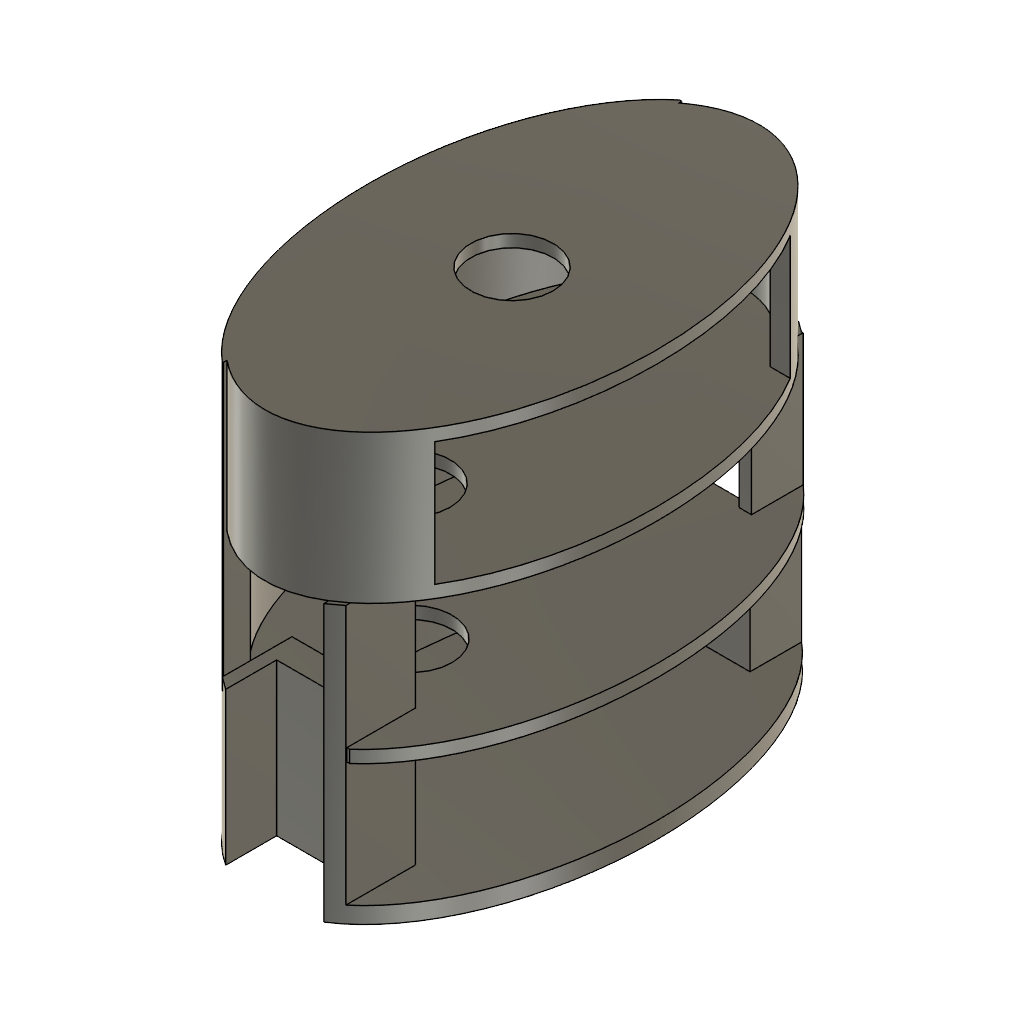
RobotBody (Autodesk Fusion 360 design; units mm, degrees)
part number: 2026-05-27-16-43-57-428
Autodesk Fusion 360 part; units mm, degrees
sketch "Sketch1" plane through (0, 0, 0) normal (0, 0, 1) x (1, 0, 0)
  line L0 (0, 45) -> (12, 45)
  line L1 (12, 45) -> (-12, 45)
  line L2 (-12, 45) -> (12.1326, 45)
  line L3 (12.1326, 45) -> (12.1326, 57.4523)
  line L4 (-12, 57.5375) -> (-12, 45)
  line L5 (-0.0989, -41.2502) -> (-12.0988, -41.3096)
  line L6 (-12.0988, -41.3096) -> (11.9009, -41.1909)
  line L7 (11.9009, -41.1909) -> (-11.9631, -41.1909)
  line L8 (-11.9631, -41.1909) -> (-11.9631, -57.561)
  line L9 (11.9009, -57.561) -> (11.9009, -41.1909)
  ellipse E0 centre (0, 0) end of major axis (35, 0) minor radius 61.25 (-12, 57.5375) -> (-11.9631, -57.561) ccw
  ellipse E1 centre (0, 0) end of major axis (35, 0) minor radius 61.25 (11.9009, -57.6005) -> (12.1326, 57.4523) ccw
  line L10 (11.9009, -41.1909) -> (11.9009, -57.6005)
  dimension "d1" = 70
  dimension "d2" = 122.5
  dimension "d3" = 12
  dimension "d4" = 24
  dimension "d6" = 12
  dimension "d7" = 24
  constraint coincident E0.centre E1.centre
  constraint horizontal L2
  constraint vertical L3
  constraint vertical L4
  constraint horizontal L7
  constraint vertical L8
  constraint vertical L9
  constraint concentric E0 E1
  constraint perpendicular L7 L10
  measures "d1" distance of E0
  measures "d3" distance of L0.start L0.end
  measures "d4" distance of L0.end L1.end
  measures "d6" distance of L5.start L5.end
  measures "d7" distance of L5.end L6.end
extrude "Extrude1" add sketch "Sketch1" along normal blind 4 contours L0 L1 L2 L3 L4 L7 L8 L9 E0 E1 L10
sketch "Sketch2" plane through (0, 0, 4) normal (0, 0, 1) x (-1, 0, 0)
  line L0 (11.9631, 41.1909) -> (-11.9009, 41.1909)
  line L1 (-11.9009, 41.1909) -> (-11.9009, 57.6005)
  ellipse E0 centre (0, 0) end of major axis (0, -61.25) minor radius 35 (-11.9009, 57.6005) -> (-12.1326, -57.4523) ccw
  line L2 (-12.1326, -57.4523) -> (-12.1326, -45)
  line L3 (-12.1326, -45) -> (12, -45)
  line L4 (12, -45) -> (12, -57.5375)
  ellipse E1 centre (0, 0) end of major axis (0, -61.25) minor radius 35 (12, -57.5375) -> (11.9631, 57.561) ccw
  line L5 (11.9631, 57.561) -> (11.9631, 41.1909)
  line L6 (14.7106, -42.8069) -> (-15, -42.8069)
  line L7 (-15, -42.8069) -> (-15, -55.3399)
  line L8 (14.7106, -55.5773) -> (14.7106, -42.8069)
  line L9 (-15, 38.4373) -> (15, 38.4373)
  line L10 (15, 38.4373) -> (15, 55.3399)
  line L11 (-15, 55.3399) -> (-15, 38.4373)
  constraint horizontal L6
  constraint vertical L7
  constraint vertical L8
  constraint horizontal L9
  constraint vertical L10
  constraint vertical L11
  constraint coincident E1 L8.start
  constraint coincident E0 L7.end
  constraint coincident E1 L10.end
  constraint coincident E0 L11.start
extrude "Extrude2" add sketch "Sketch2" along normal blind 20 contours L0 L1 E0 E1 L5 L9 L10 L11 | E0 L2 L3 L4 E1 L6 L7 L8
sketch "Sketch3" plane through (0, 0, 4) normal (0, 0, 1) x (-1, 0, 0)
  line L0 (15, 55.3399) -> (15, 38.4373)
  line L1 (15, 38.4373) -> (-15, 38.4373)
  line L2 (-15, 38.4373) -> (-15, 55.3399)
  ellipse E0 centre (0, 0) end of major axis (0, -61.25) minor radius 35 (-15, 55.3399) -> (-15, -55.3399) ccw
  line L3 (-15, -55.3399) -> (-15, -42.8069)
  line L4 (-15, -42.8069) -> (14.7106, -42.8069)
  line L5 (14.7106, -42.8069) -> (14.7106, -55.5773)
  ellipse E1 centre (0, 0) end of major axis (0, -61.25) minor radius 35 (14.7106, -55.5773) -> (15, 55.3399) ccw
  ellipse E2 centre (0, 0) end of major axis (-30, 0) minor radius 55 (14.7106, -47.9339) -> (15, 47.6314) ccw
  ellipse E3 centre (0, 0) end of major axis (-30, 0) minor radius 55 (-15, 47.6314) -> (-15, -47.6314) ccw
  constraint coincident E0.centre E1.centre
  constraint concentric E2 E3
extrude "Extrude3" add sketch "Sketch3" along normal blind 80 contours L0 L5 E1 E2
extrude "Extrude4" cut 1 faces at (-29.9367, -18.1524, 84) along direction (0, 0, -1) blind 40
extrude "Extrude5" cut 1 faces at (-29.9367, -18.1524, 44) along direction (0, 0, -1) blind 10
sketch "Sketch4" plane through (0, 0, 34) normal (0, 0, 1) x (-1, 0, 0)
  ellipse E0 centre (0, 0) end of major axis (0, -55) minor radius 30 (14.7106, -47.9339) -> (15, 47.6314) ccw
  line L0 (14.7106, -47.9339) -> (14.7106, -55.5773)
  ellipse E1 centre (0, 0) end of major axis (0, -61.25) minor radius 35 (14.7106, -55.5773) -> (15, 55.3399) ccw
  line L1 (15, 55.3399) -> (15, 47.6314)
  line L2 (15.3224, 37.9496) -> (-15.6787, 37.9496)
  line L3 (-15.6787, 37.9496) -> (-15.6787, 55.1146)
  line L4 (15.3224, 55.4246) -> (15.3224, 37.9496)
  line L5 (-15.1442, -42.4038) -> (14.7879, -42.4038)
  line L6 (14.7879, -42.4038) -> (14.7879, -55.8732)
  line L7 (-15.1442, -55.5763) -> (-15.1442, -42.4038)
  ellipse E2 centre (0, 0) end of major axis (35, 0) minor radius 61.6458 (-15.6787, 55.1146) -> (-15.1442, -55.5763) ccw
  ellipse E3 centre (0, 0) end of major axis (35, 0) minor radius 61.6458 (14.7879, -55.8732) -> (15.3224, 55.4246) ccw
  constraint coincident E0.centre E1.centre
  constraint horizontal L2
  constraint vertical L3
  constraint vertical L4
  constraint horizontal L5
  constraint vertical L6
  constraint vertical L7
  constraint concentric E2 E3
extrude "Extrude6" add sketch "Sketch4" along normal blind 3 contours E0 L2 L3 L4 L5 L6 L7 E2 | E0 E1 L4 L6
hole "Hole1" at (-0.0979, -24.4642, 37) direction (0, 0, -1) diameter 20 depth 25 tip angle 118
sketch "Sketch5" plane through (0, 0, 37) normal (0, 0, 1) x (-1, 0, 0)
  circle A0 centre (0.0979, 24.4642) radius 10
  line L0 (-15.1442, -42.4038) -> (14.7879, -42.4038)
  line L1 (14.7879, -42.4038) -> (14.7879, -55.5144)
  ellipse E0 centre (0, 0) end of major axis (0, -61.25) minor radius 35 (14.7879, -55.5144) -> (15.3224, 55.0687) ccw
  line L2 (15.3224, 55.0687) -> (15.3224, 37.9496)
  line L3 (15.3224, 37.9496) -> (-15.6787, 37.9496)
  line L4 (-15.6787, 37.9496) -> (-15.6787, 55.1146)
  ellipse E1 centre (0, 0) end of major axis (0, 61.6458) minor radius 35 (-15.6787, 55.1146) -> (-15.1442, -55.5763) ccw
  line L5 (-15.1442, -55.5763) -> (-15.1442, -42.4038)
  ellipse E2 centre (0, 0) end of major axis (30, 0) minor radius 56.4175 (14.7879, -49.0871) -> (15.3224, 48.5039) ccw
  constraint coincident E0.centre E1.centre
extrude "Extrude7" add sketch "Sketch5" along normal blind 30 contours L1 E0 L2 E2
sketch "Sketch6" plane through (0, 0, 67) normal (0, 0, 1) x (-1, 0, 0)
  ellipse E0 centre (0, 0) end of major axis (0, 56.4175) minor radius 30 (14.7879, -49.0871) -> (15.3224, 48.5039) ccw
  line L0 (14.7879, -49.0871) -> (14.7879, -55.5144)
  ellipse E1 centre (0, 0) end of major axis (0, -61.25) minor radius 35 (14.7879, -55.5144) -> (15.3224, 55.0687) ccw
  line L1 (15.3224, 55.0687) -> (15.3224, 48.5039)
  ellipse E2 centre (0, 0) end of major axis (35, 0) minor radius 60
  line L2 (-35, 0) -> (35, 0) construction
  line L3 (0, -60) -> (0, 60) construction
  circle A0 centre (0, 25) radius 10
  dimension "d25" = 20
  constraint coincident E2 L2.start
  constraint coincident E2 L2.end
  constraint coincident E2 L3.start
  constraint coincident E2 L3.end
  constraint coincident E0.centre E1.centre
  constraint horizontal L2
  constraint coincident L3 A0.centre
  measures "d25" diameter of A0
extrude "Extrude8" add sketch "Sketch6" along normal blind 3 contours E0 L0 L1 E2 | E0 L0 L1 E2
extrude "Extrude9" add 1 faces at (13.967, -44.9894, 24) along direction (0, 0, 1) blind 13
extrude "Extrude10" add 1 faces at (15.6787, -43.6712, 35) along direction (-1, 0, 0) blind 0.678
extrude "Extrude11" add 1 faces at (-5.2147, -37.9496, 36) along direction (0, -1, 0) blind 0.48
extrude "Extrude12" add 1 faces at (-15.3224, -52.5058, 47) along direction (1, 0, 0) blind 0.322
sketch "Sketch7" plane through (0, 0, 37) normal (0, 0, 1) x (-1, 0, 0)
  line L0 (-15, 55.3399) -> (-15, 38.4373)
  line L1 (-15, 38.4373) -> (15, 38.4373)
  line L2 (15, 38.4373) -> (15, 55.3399)
  ellipse E0 centre (0, 0) end of major axis (0, -61.25) minor radius 35 (15, 55.3399) -> (11.9631, 57.561) ccw
  line L3 (11.9631, 57.561) -> (11.9631, 41.1909)
  line L4 (11.9631, 41.1909) -> (-11.9009, 41.1909)
  line L5 (-11.9009, 41.1909) -> (-11.9009, 57.6005)
  ellipse E1 centre (0, 0) end of major axis (0, -61.25) minor radius 35 (-11.9009, 57.6005) -> (-15, 55.3399) ccw
  line L6 (-11.9009, 38.4296) -> (-15, 38.4296)
  line L7 (-15, 38.4296) -> (-15, 55.3399)
  line L8 (-11.9009, 57.6005) -> (-11.9009, 38.4296)
  line L9 (-15.0007, 38.4296) -> (15.0004, 38.4296)
  constraint horizontal L6
  constraint vertical L7
  constraint vertical L8
  constraint coincident L6.start L9
extrude "Extrude13" add sketch "Sketch7" along normal blind 30 contours L0 L1 L5 E1 L7 L8
extrude "Extrude14" add 1 faces at (14.0442, 47.7156, 24) along direction (0, 0, 1) blind 13
extrude "Extrude15" add 1 faces at (15.1442, 51.1854, 35) along direction (-1, 0, 0) blind 0.14
extrude "Extrude16" cut 1 faces at (5.0735, 42.4038, 35) along direction (0, 1, 0) blind 0.9
extrude "Extrude17" add 1 faces at (5.0735, 42.4038, 35) along direction (0, 1, 0) blind 0.9
extrude "Extrude18" add 2 faces at (15.0028, 43.3038, 35) (15.0042, 51.4854, 35) along direction (-1, 0, 0) blind 0.9
extrude "Extrude19" add 1 faces at (-14.7879, 52.9944, 47) along direction (1, 0, 0) blind 0.5
sketch "Sketch8" plane through (0, 0, 37) normal (0, 0, 1) x (-1, 0, 0)
  circle A0 centre (0.0979, 24.4642) radius 10
  line L0 (14.7106, -55.5144) -> (14.2879, -55.5144)
  line L1 (14.2879, -55.5144) -> (14.2879, -49.0871)
  line L2 (14.2879, -49.0871) -> (14.7879, -49.0871)
  ellipse E0 centre (0, 0) end of major axis (0, 56.4175) minor radius 30 (14.7879, -49.0871) -> (15.3224, 48.5039) ccw
  line L3 (15.3224, 48.5039) -> (15.0004, 48.5039)
  line L4 (15.0004, 48.5039) -> (15.0004, 38.4296)
  line L5 (15.0004, 38.4296) -> (-15.0007, 38.4296)
  line L6 (-15.0007, 38.4296) -> (-15.0007, 55.1146)
  line L7 (-15.0007, 55.1146) -> (-15.6787, 55.1146)
  ellipse E1 centre (0, 0) end of major axis (0, 61.6458) minor radius 35 (-15.6787, 55.1146) -> (-15.1442, -55.5763) ccw
  line L8 (-15.1442, -55.5763) -> (-14.7118, -55.5763)
  ellipse E2 centre (0, 0) end of major axis (0, -61.25) minor radius 35 (-14.7118, -55.5763) -> (-12.1326, -57.4523) ccw
  line L9 (-12.1326, -57.4523) -> (-12.1326, -45)
  line L10 (-12.1326, -45) -> (12, -45)
  line L11 (12, -45) -> (12, -57.5375)
  ellipse E3 centre (0, 0) end of major axis (0, -61.25) minor radius 35 (12, -57.5375) -> (14.7106, -55.5773) ccw
  line L12 (14.7106, -55.5773) -> (14.7106, -55.5144)
  line L13 (-12.1326, -45) -> (-15.1442, -45)
  line L14 (-15.1442, -45) -> (-15.1442, -55.5763)
  line L15 (-12.1326, -57.4523) -> (-12.1326, -45)
  constraint horizontal L13
  constraint vertical L14
  constraint vertical L15
  constraint coincident L9.end L10.start
extrude "Extrude20" add sketch "Sketch8" along normal blind 32 contours L8 E2 L9 L13 L14 L15
extrude "Extrude21" add 1 faces at (13.1364, 45, 57) along direction (0, -1, 0) blind 2
extrude "Extrude22" add 1 faces at (3.9463, -41.1909, 24.6667) along direction (0, -1, 0) blind 4
extrude "Extrude23" add 1 faces at (3.967, -38.4373, 15) along direction (0, -1, 0) blind 4
sketch "Sketch9" plane through (0, 0, 70) normal (0, 0, 1) x (-1, 0, 0)
  circle A0 centre (0, 25) radius 10
  ellipse E0 centre (0, 0) end of major axis (0, 60) minor radius 35
  line L0 (-19.2935, -43.3897) -> (-24.1738, -43.3897)
  line L1 (-19.4797, 43.0919) -> (-24.3543, 43.0919)
  ellipse E1 centre (0, 0) end of major axis (30, 0) minor radius 56.6617 (-19.2935, -43.3897) -> (-19.4797, 43.0919) ccw
  constraint coincident E0.centre E1.centre
  constraint coincident E0 L0.end
  constraint horizontal L0
  constraint coincident E0 L1.end
  constraint horizontal L1
extrude "Extrude24" add sketch "Sketch9" along normal blind 30 contours E0 L0 L1 E1 picked at (30.7182, 12.9741)
sketch "Sketch10" plane through (0, 0, 100) normal (0, 0, 1) x (-1, 0, 0)
  ellipse E0 centre (0, 0) end of major axis (0, 56.6617) minor radius 30 (-19.2935, -43.3897) -> (-19.4797, 43.0919) ccw
  line L0 (-19.2935, -43.3897) -> (-24.1738, -43.3897)
  ellipse E1 centre (0, 0) end of major axis (0, 60) minor radius 35 (-24.1738, -43.3897) -> (-24.3543, 43.0919) ccw
  line L1 (-24.3543, 43.0919) -> (-19.4797, 43.0919)
  ellipse E2 centre (0, 0) end of major axis (35, 0) minor radius 60
  line L2 (-35, 0) -> (35, 0) construction
  line L3 (0, -60) -> (0, 60) construction
  circle A0 centre (0, 0) radius 10
  constraint coincident E2 L2.start
  constraint coincident E2 L2.end
  constraint coincident E2 L3.start
  constraint coincident E2 L3.end
  constraint coincident E0.centre E1.centre
  constraint horizontal L2
extrude "Extrude25" add sketch "Sketch10" along normal blind 3
extrude "Extrude26" add 2 faces at (-16.0366, 53.951, 67) (-16.7912, -52.9668, 67) along direction (0, 0, 1) blind 36
